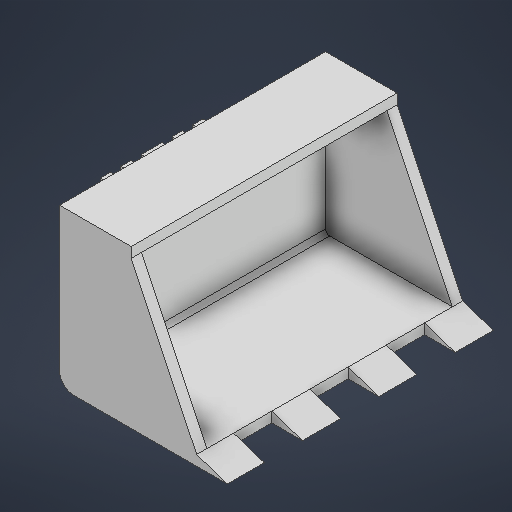
# Autodesk Inventor part: Pala
Saved by Autodesk Inventor 2027.1 (Build 311270010, 270A)
## iProperties
Created: 2026-10-01
Part Number: Pala
Material: Genérico
Document SubType Name: Modeling
Designer: irene
Density: 1 g/cm^3
Appearance: Valor por defecto
Author: irene
Autodesk Inventor part; units mm, degrees
ref_plane "YZ Plane" through (0, 0, 0) normal (1, 0, 0) x (0, 1, 0)
ref_plane "XZ Plane" through (0, 0, 0) normal (0, 1, 0) x (-1, 0, 0)
ref_plane "XY Plane" through (0, 0, 0) normal (0, 0, 1) x (1, 0, 0)
sketch "Boceto1" plane through (0, 0, 0) normal (0, 0, 1) x (1, 0, 0)
  line L0 (0, 2) -> (0, 67)
  line L1 (2, 0) -> (62, 0)
  arc A0 (0, 2) -> (2, 0) centre (2, 2) ccw
  line L2 (0, 67) -> (30, 67)
  line L3 (30, 67) -> (62, 0)
  line L4 (30, 72) -> (-5, 72)
  line L5 (-5, 72) -> (-5, 2)
  arc A1 (-5, 2) -> (2, -5) centre (2, 2) ccw
  line L6 (2, -5) -> (62, -5)
  line L7 (30, 67) -> (30, 72)
  line L8 (62, 0) -> (62, -5)
  point P0 (0, 0)
  point P1 (0, 34.5)
  dimension "d0" = 2
  dimension "d1" = 65
  dimension "d2" = 60
  dimension "d3" = 30
  dimension "d4" = 5
  dimension "d5" = 5
  dimension "d6" = 5
  constraints: 18 end point, 4 point on circle, 2 centre point, 2 horizontal, 2 perpendicular, 2 point on line, 2 tangent, 1 midpoint, 1 vertical, 1 other
  measures "d0" radius of A0
  measures "d1" distance of L0.start L0.end
  measures "d2" distance of L1.start L1.end
  measures "d3" distance of L0.end L2.end
  measures "d4" distance between parallel lines of L2 L4
  measures "d5" distance from line of point (0, 34.5) L5
  measures "d6" distance between parallel lines of L1 L6
extrude "Extrusión1" add sketch "Boceto1" along normal mid plane 120 contours A0 L1 L8 L6 A1 L5 L4 L7 L2 L0
sketch "Boceto2" plane through (0, 0, 60) normal (0, 0, 1) x (1, 0, 0)
  line L0 (0, 2) -> (0, 67) projected
  line L1 (0, 67) -> (30, 67) projected
  line L2 (30, 67) -> (30, 72) projected
  line L3 (30, 72) -> (-5, 72) projected
  line L4 (-5, 72) -> (-5, 2) projected
  arc A0 (-5, 2) -> (2, -5) centre (2, 2) ccw projected
  line L5 (2, -5) -> (62, -5) projected
  line L6 (62, -5) -> (62, 0) projected
  line L7 (62, 0) -> (2, 0) projected
  arc A1 (0, 2) -> (2, 0) centre (2, 2) ccw projected
  line L8 (30, 67) -> (62, 0)
  point P0 (0, 0)
  constraints: 2 end point
extrude "Extrusión2" add sketch "Boceto2" along normal blind 5
sketch "Boceto3" plane through (0, 0, -60) normal (0, 0, -1) x (-1, 0, 0)
  line L0 (0, 67) -> (-30, 67) projected
  line L1 (-62, 0) -> (-2, 0) projected
  line L2 (-30, 67) -> (-62, 0)
  line L3 (0, 67) -> (0, 2) projected
  arc A0 (-2, 0) -> (0, 2) centre (-2, 2) ccw projected
  line L4 (-2, 0) -> (-62, 0) projected
  line L5 (-62, 0) -> (-62, -5) projected
  line L6 (-62, -5) -> (-2, -5) projected
  arc A1 (-2, -5) -> (5, 2) centre (-2, 2) ccw projected
  line L7 (5, 2) -> (5, 72) projected
  line L8 (5, 72) -> (-30, 72) projected
  line L9 (-30, 72) -> (-30, 67) projected
  line L10 (-30, 67) -> (0, 67) projected
  point P0 (0, 0)
  constraints: 2 end point
extrude "Extrusión3" add sketch "Boceto3" along normal blind 5
sketch "Boceto4" plane through (0, 0, 65) normal (0, 0, 1) x (1, 0, 0)
  line L0 (2, -5) -> (62, -5) projected
  line L1 (62, -5) -> (77, -5)
  line L2 (62, -5) -> (62, 0) projected
  line L3 (62, 0) -> (77, -5)
  point P0 (0, 0)
  dimension "d13" = 15
  constraints: 4 end point, 1 horizontal
  measures "d13" distance of L0.end L1.end
extrude "Extrusión4" add sketch "Boceto4" against normal blind 20
sketch "Boceto5" plane through (0, 0, -65) normal (0, 0, -1) x (-1, 0, 0)
  line L0 (-62, 0) -> (-77, -5) projected
  line L1 (-77, -5) -> (-62, -5) projected
  line L2 (-62, 0) -> (-62, -5) projected
  point P0 (0, 0)
extrude "Extrusión5" add sketch "Boceto5" against normal blind 20
sketch "Boceto6" plane through (0, 0, -45) normal (0, 0, 1) x (1, 0, 0)
  line L0 (62, -5) -> (77, -5) projected
  line L1 (77, -5) -> (62, 0) projected
  line L2 (62, -5) -> (62, 0) projected
  point P0 (0, 0)
extrude "Extrusión6" add sketch "Boceto6" along normal up to surface (90 mm away)
sketch "Boceto7" plane through (2, -5, -65) normal (0, -1, 0) x (1, 0, 0)
  line L0 (60, 5) -> (60, 0) projected
  line L1 (60, 0) -> (60, 129.6592)
  line L2 (60, 18.66) -> (75, 18.66)
  line L3 (75, 130) -> (75, 0) projected
  line L4 (60, 5) -> (60, 125) projected
  line L5 (60, 37.32) -> (75, 37.32)
  line L6 (60, 74.64) -> (75, 74.64)
  line L7 (60, 93.3) -> (75, 93.3)
  line L8 (75, 0) -> (0, 0) projected
  line L9 (60, 55.98) -> (75, 55.98)
  line L10 (60, 130.16) -> (75, 130.16)
  line L11 (60, 111.96) -> (75, 111.96)
  line L12 (0, 130) -> (75, 130) projected
  point P0 (-2, 65)
  point P1 (67.5, 55.98)
  dimension "d20" = 18.66
  dimension "d21" = 18.66
  dimension "d22" = 18.66
  dimension "d27" = 18.66
  dimension "d28" = 18.66
  dimension "d29" = 18.66
  dimension "d30" = 18.2
  constraints: 16 end point, 7 point on line, 5 perpendicular, 2 horizontal, 1 midpoint, 1 vertical, 7 other
  measures "d20" distance between parallel lines of L8 L2
  measures "d21" distance between parallel lines of L5 L2
  measures "d22" distance from line of L5 point (67.5, 55.98)
  measures "d27" distance between parallel lines of L9 L6
  measures "d28" distance between parallel lines of L6 L7
  measures "d29" distance between parallel lines of L7 L11
  measures "d30" distance between parallel lines of L10 L11
extrude "Extrusión7" cut sketch "Boceto7" against normal blind 10 contours L1 L5 L3 L2 | L1 L6 L3 L9 | L1 L11 L3 L7
sketch "Boceto8" plane through (-5, 2, 65) normal (-1, 0, 0) x (0, 0, 1)
  line L0 (-55, 11.5) -> (-75, 11.5)
  line L1 (-75, 11.5) -> (-75, 51.5)
  line L2 (-75, 51.5) -> (-55, 51.5)
  line L3 (-55, 51.5) -> (-55, 11.5)
  line L4 (-55, 11.5) -> (-75, 51.5) construction
  line L5 (-75, 11.5) -> (-55, 51.5) construction
  line L6 (-130, 70) -> (0, 70) projected
  line L7 (0, -2) -> (0, 65) projected
  line L8 (-75, 31.5) -> (-80, 31.5) construction
  line L9 (-55, 31.5) -> (-50, 31.5) construction
  line L10 (-85, 51.5) -> (-80, 51.5)
  line L11 (-80, 51.5) -> (-80, 11.5)
  line L12 (-80, 11.5) -> (-85, 11.5)
  line L13 (-85, 11.5) -> (-85, 51.5)
  line L14 (-85, 51.5) -> (-80, 11.5) construction
  line L15 (-80, 51.5) -> (-85, 11.5) construction
  line L16 (-50, 51.5) -> (-45, 51.5)
  line L17 (-45, 51.5) -> (-45, 11.5)
  line L18 (-45, 11.5) -> (-50, 11.5)
  line L19 (-50, 11.5) -> (-50, 51.5)
  line L20 (-50, 51.5) -> (-45, 11.5) construction
  line L21 (-45, 51.5) -> (-50, 11.5) construction
  line L22 (-80, 51.5) -> (-75, 51.5)
  line L23 (-80, 11.5) -> (-75, 11.5)
  line L24 (-55, 11.5) -> (-50, 11.5)
  line L25 (-55, 51.5) -> (-50, 51.5)
  line L26 (-75, 51.5) -> (-70, 51.5)
  line L27 (-70, 51.5) -> (-70, 11.5)
  line L28 (-55, 51.5) -> (-60, 51.5)
  line L29 (-60, 51.5) -> (-60, 11.5)
  line L30 (-70, 51.5) -> (-65, 51.5)
  line L31 (-65, 51.5) -> (-65, 11.5)
  line L32 (-85, 51.5) -> (-90, 51.5)
  line L33 (-90, 51.5) -> (-90, 11.5)
  line L34 (-90, 11.5) -> (-85, 11.5)
  line L35 (-45, 11.5) -> (-40, 11.5)
  line L36 (-40, 11.5) -> (-40, 51.5)
  line L37 (-40, 51.5) -> (-45, 51.5)
  point P0 (-65, -2)
  point P1 (-65, 31.5)
  point P2 (-65, 70)
  point P3 (0, 31.5)
  point P4 (-82.5, 31.5)
  point P5 (-47.5, 31.5)
  dimension "d34" = 20
  dimension "d35" = 40
  dimension "d36" = 5
  dimension "d37" = 5
  dimension "d38" = 5
  dimension "d39" = 5
  dimension "d40" = 40
  dimension "d41" = 40
  dimension "d42" = 5
  dimension "d43" = 5
  dimension "d54" = 5
  dimension "d55" = 5
  dimension "d56" = 5
  dimension "d57" = 5
  dimension "d58" = 5
  constraints: 72 end point, 13 midpoint, 8 perpendicular, 6 horizontal, 6 parallel, 6 point on line, 3 horizontal alignment, 1 vertical alignment
  measures "d34" distance of L1.end L2.end
  measures "d35" distance of L2.end L0.start
  measures "d36" distance of L8.start L8.end
  measures "d37" distance of L9.start L9.end
  measures "d38" distance of L10.start L10.end
  measures "d39" distance of L16.start L16.end
  measures "d40" distance of L10.end L11.end
  measures "d41" distance of L18.end L16.start
  measures "d42" distance of L8.start point (-80, 31.5)
  measures "d43" distance between parallel lines of L3 L19
  measures "d54" distance of L1.end L26.end
  measures "d55" distance of L2.end L28.end
  measures "d56" distance of L26.end L30.end
  measures "d57" distance of L10.start L32.end
  measures "d58" distance of L17.end L35.end
extrude "Extrusión8" add sketch "Boceto8" along normal blind 20 contours L3 L25 L19 L24 | L0 L31 L2 L29 | L0 L27 L2 L31 | L17 L37 L36 L35 | L23 L11 L22 L1 | L34 L33 L32 L13
fillet "Empalme3" radius 2 8 edges at (-5, 13.5, -12.5) (-5, 33.5, -15) (-5, 33.5, -10) (-5, 13.5, 12.5) (-5, 33.5, 15) (-5, 33.5, 10) (-5, 53.5, -12.5) (-5, 53.5, 12.5)
fillet "Empalme4" radius 2 12 edges at (-5, 53.5, 0) (-5, 13.5, 0) (-5, 33.5, -5) (-5, 33.5, 5) (-5, 13.5, 22.5) (-5, 33.5, 20) (-5, 33.5, 25) (-5, 53.5, 22.5) (-5, 13.5, -22.5) (-5, 33.5, -25) (-5, 33.5, -20) (-5, 53.5, -22.5)
sketch "Boceto10" plane through (-25, 13.5, -25) normal (0, 0, -1) x (-1, 0, 0)
  circle A0 centre (-8, 20) radius 2.5
  line L0 (-18, 40) -> (0, 40) projected
  line L1 (-18, 0) -> (-18, 40) projected
  point P0 (-25, -13.5)
  dimension "d60" = 5
  dimension "d61" = 20
  dimension "d62" = 10
  constraints: 1 centre point
  measures "d60" diameter of A0
  measures "d61" distance from line of L0 A0.centre
  measures "d62" distance from line of L1 A0.centre
extrude "Extrusión10" cut sketch "Boceto10" against normal through all
